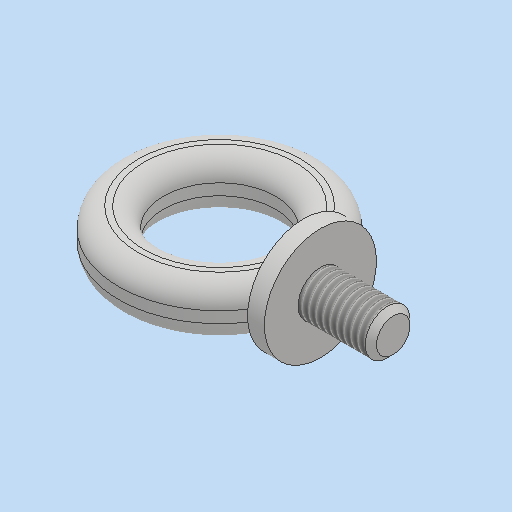
# Autodesk Inventor part: MM0861AN200_G22_311
Saved by Autodesk Inventor 2023.3 (Build 273359000, 359)
## iProperties
Part Number: MM0861AN200_G22_311
Material: Generisch
Description: =<RBPARTNOTITLE2>
Document SubType Name: Modeling
Designer: Benutzer
Mass: 6.72116 g
Surface Area: 32.3387 cm^2
Volume: 6.72116 cm^3
Density: 1 g/cm^3
Appearance: Vorgabe
Vendor: Wuerth
RBDOCUMENTTYPE: DRF
RBDOCUMENTVERSION: 00
RBDRAWINGMAINSCALE: 1:1
RBDRAWINGMISSINGSPEC: --
RBDRAWINGVOLUME: --
RBGBEDGESIN1: +0,5
RBGBEDGESIN2: +0,2
RBGBEDGESOUT1: -0,3
RBGBEDGESOUT2: -0,1
RBMATERIAL: --
RBMATMEETS: --
RBMATNO: =<Part Number>
RBPARTMADEOF: 029598
RBPARTNO: SIEHE MNR
RBPARTNOTITLE1: enter description here
RBPARTNOTITLE2: Ringschraube
RBPARTSAFETYINDICATOR: --
RBSURFACE: --
RBSURFACE2: --
RBZEDGESNORM: ISO13715:2002-06
RBZGENDIMCLASS: m
RBZGENDIMNORM: ISO 2768-1:1989-11
RBZGENGEOCLASS: H
RBZGENGEONORM: ISO 2768-2:1989-11
RBZSURFACENORM: ISO13D2:2002-02
RBZTOLERANCENORM: ISO 14405-1:2010-12
AnP_Material: =<Material>
AnP_TemplVers: 20190222
AnP_Kategorie: 2
Author: Benutzer
Keywords: =<RBPARTMADEOF>
Comments: =<RBSURFACE2>
Revision Number: 01
Autodesk Inventor part; units mm, degrees
ref_plane "XZ Plane" through (0, 0, 0) normal (0, 1, 0) x (-1, 0, 0)
ref_plane "XY Plane" through (0, 0, 0) normal (0, 0, 1) x (1, 0, 0)
sketch "Skizze1" plane through (0, 0, 0) normal (0, 0, 1) x (1, 0, 0)
  circle A0 centre (0, 0) radius 10
  circle A1 centre (0, 0) radius 18
  dimension "d0" = 20
  dimension "d1" = 36
  constraints: 2 centre point, 2 coincident
  measures "d0" diameter of A0
  measures "d1" diameter of A1
extrude "Extrusion1" add sketch "Skizze1" along normal blind 9
fillet "Rundung1" radius 3.5 4 edges at (-10, 0, 9) (-18, 0, 9) (-18, 0, 0) (-10, 0, 0)
ref_plane "Arbeitsebene1" through (15, 0, 0) normal (1, 0, 0) x (0, 1, 0)
sketch "Skizze2" plane through (15, 0, 0) normal (1, 0, 0) x (0, 1, 0)
  circle A0 centre (0, 4.5) radius 10
  line L0 (-14.5, 9) -> (14.5, 9) projected
  point P0 (0, 0)
  dimension "d6" = 20
  dimension "d7" = 4.5
  constraints: 1 centre point, 1 coincident
  measures "d6" diameter of A0
  measures "d7" distance from line of A0.centre L0
extrude "Extrusion2" add sketch "Skizze2" along normal blind 3
sketch "Skizze3" plane through (18, 0, 4.5) normal (1, 0, 0) x (0, 0, -1)
  circle A0 centre (0, 0) radius 4
  point P0 (4.5, 0)
  dimension "d10" = 8
  constraints: 1 centre point
  measures "d10" diameter of A0
extrude "Extrusion3" add sketch "Skizze3" along normal blind 13
thread "Gewinde1" size "M8x1.25" designation "M8" class "6g" standard "ISO Metric profile" full length
chamfer "Fase1" distance 1 angle 45 1 edges at (31, 0, 8.5)
ref_plane "Arbeitsebene2" through (19, 0, 0) normal (1, 0, 0) x (0, 1, 0)
